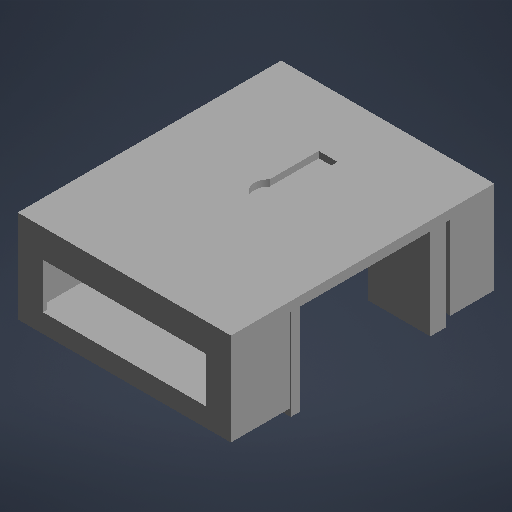
# Autodesk Inventor part: R2_pelvis
Saved by Autodesk Inventor 2027 (Build 310192060, 192F)
## iProperties
Part Number: R2_pelvis
Material: Genérico
Document SubType Name: Modelado
Designer: rodri
Appearance: Por defecto
Author: rodri
Autodesk Inventor part; units mm, degrees
ref_plane "Plano de trabajo1" through (0, 0, -38) normal (0, 0, 1) x (1, 0, 0)
sketch "Boceto1" plane through (0, 0, -38) normal (0, 0, 1) x (1, 0, 0)
  line L0 (-34, -3) -> (34, -3)
  line L1 (34, -3) -> (34, 0)
  line L2 (34, 0) -> (-34, 0)
  line L3 (-34, 0) -> (-34, -3)
  constraints: 8 end point, 2 parallel, 1 horizontal, 1 perpendicular
extrude "Extrusión1" add sketch "Boceto1" along normal blind 84
ref_plane "Plano de trabajo2" through (0, -2, 0) normal (0, 1, 0) x (-1, 0, 0)
sketch "Boceto2" plane through (0, -2, 0) normal (0, 1, 0) x (-1, 0, 0)
  circle A0 centre (0, 0) radius 4.5
  constraints: 1 centre point
extrude "Extrusión2" cut sketch "Boceto2" along normal blind 2.1
ref_plane "Plano de trabajo3" through (0, 0, -19) normal (0, 0, 1) x (1, 0, 0)
sketch "Boceto3" plane through (0, 0, -19) normal (0, 0, 1) x (1, 0, 0)
  line L0 (-3, -2) -> (3, -2)
  line L1 (3, -2) -> (3, 0.1)
  line L2 (3, 0.1) -> (-3, 0.1)
  line L3 (-3, 0.1) -> (-3, -2)
  constraints: 8 end point, 2 parallel, 1 horizontal, 1 perpendicular
extrude "Extrusión3" cut sketch "Boceto3" along normal blind 22
ref_plane "Plano de trabajo4" through (0, 0, 44.5) normal (0, 0, 1) x (1, 0, 0)
sketch "Boceto4" plane through (0, 0, 44.5) normal (0, 0, 1) x (1, 0, 0)
  line L0 (-34, -29.5) -> (34, -29.5)
  line L1 (34, -29.5) -> (34, -2.9)
  line L2 (34, -2.9) -> (-34, -2.9)
  line L3 (-34, -2.9) -> (-34, -29.5)
  constraints: 8 end point, 2 parallel, 1 horizontal, 1 perpendicular
extrude "Extrusión4" add sketch "Boceto4" along normal blind 1.5
ref_plane "Plano de trabajo5" through (0, 0, 27) normal (0, 0, 1) x (1, 0, 0)
sketch "Boceto5" plane through (0, 0, 27) normal (0, 0, 1) x (1, 0, 0)
  line L0 (-34, -29.5) -> (34, -29.5)
  line L1 (34, -29.5) -> (34, -27)
  line L2 (34, -27) -> (-34, -27)
  line L3 (-34, -27) -> (-34, -29.5)
  constraints: 8 end point, 2 parallel, 1 horizontal, 1 perpendicular
extrude "Extrusión5" add sketch "Boceto5" along normal blind 19
ref_plane "Plano de trabajo6" through (0, 0, 27) normal (0, 0, 1) x (1, 0, 0)
sketch "Boceto6" plane through (0, 0, 27) normal (0, 0, 1) x (1, 0, 0)
  line L0 (-34, -29.5) -> (-31.5, -29.5)
  line L1 (-31.5, -29.5) -> (-31.5, -2.9)
  line L2 (-31.5, -2.9) -> (-34, -2.9)
  line L3 (-34, -2.9) -> (-34, -29.5)
  constraints: 8 end point, 2 parallel, 1 horizontal, 1 perpendicular
extrude "Extrusión6" add sketch "Boceto6" along normal blind 19
ref_plane "Plano de trabajo7" through (0, 0, 27) normal (0, 0, 1) x (1, 0, 0)
sketch "Boceto7" plane through (0, 0, 27) normal (0, 0, 1) x (1, 0, 0)
  line L0 (31.5, -29.5) -> (34, -29.5)
  line L1 (34, -29.5) -> (34, -2.9)
  line L2 (34, -2.9) -> (31.5, -2.9)
  line L3 (31.5, -2.9) -> (31.5, -29.5)
  constraints: 8 end point, 2 parallel, 1 horizontal, 1 perpendicular
extrude "Extrusión7" add sketch "Boceto7" along normal blind 19
ref_plane "Plano de trabajo8" through (0, 0, 44.4) normal (0, 0, 1) x (1, 0, 0)
sketch "Boceto8" plane through (0, 0, 44.4) normal (0, 0, 1) x (1, 0, 0)
  line L0 (-26, -23.5) -> (26, -23.5)
  line L1 (26, -23.5) -> (26, -9)
  line L2 (26, -9) -> (-26, -9)
  line L3 (-26, -9) -> (-26, -23.5)
  constraints: 8 end point, 2 parallel, 1 horizontal, 1 perpendicular
extrude "Extrusión8" cut sketch "Boceto8" along normal blind 1.7
ref_plane "Plano de trabajo9" through (0, 0, -38) normal (0, 0, 1) x (1, 0, 0)
sketch "Boceto9" plane through (0, 0, -38) normal (0, 0, 1) x (1, 0, 0)
  line L0 (-34, -29.5) -> (34, -29.5)
  line L1 (34, -29.5) -> (34, -2.9)
  line L2 (34, -2.9) -> (-34, -2.9)
  line L3 (-34, -2.9) -> (-34, -29.5)
  constraints: 8 end point, 2 parallel, 1 horizontal, 1 perpendicular
extrude "Extrusión9" add sketch "Boceto9" along normal blind 2
ref_plane "Plano de trabajo10" through (0, 0, -38) normal (0, 0, 1) x (1, 0, 0)
sketch "Boceto10" plane through (0, 0, -38) normal (0, 0, 1) x (1, 0, 0)
  line L0 (-34, -29.5) -> (34, -29.5)
  line L1 (34, -29.5) -> (34, -27)
  line L2 (34, -27) -> (-34, -27)
  line L3 (-34, -27) -> (-34, -29.5)
  constraints: 8 end point, 2 parallel, 1 horizontal, 1 perpendicular
extrude "Extrusión10" add sketch "Boceto10" along normal blind 14
ref_plane "Plano de trabajo11" through (0, 0, -38) normal (0, 0, 1) x (1, 0, 0)
sketch "Boceto11" plane through (0, 0, -38) normal (0, 0, 1) x (1, 0, 0)
  line L0 (-34, -29.5) -> (-31.5, -29.5)
  line L1 (-31.5, -29.5) -> (-31.5, -2.9)
  line L2 (-31.5, -2.9) -> (-34, -2.9)
  line L3 (-34, -2.9) -> (-34, -29.5)
  constraints: 8 end point, 2 parallel, 1 horizontal, 1 perpendicular
extrude "Extrusión11" add sketch "Boceto11" along normal blind 14
ref_plane "Plano de trabajo12" through (0, 0, -38) normal (0, 0, 1) x (1, 0, 0)
sketch "Boceto12" plane through (0, 0, -38) normal (0, 0, 1) x (1, 0, 0)
  line L0 (31.5, -29.5) -> (34, -29.5)
  line L1 (34, -29.5) -> (34, -2.9)
  line L2 (34, -2.9) -> (31.5, -2.9)
  line L3 (31.5, -2.9) -> (31.5, -29.5)
  constraints: 8 end point, 2 parallel, 1 horizontal, 1 perpendicular
extrude "Extrusión12" add sketch "Boceto12" along normal blind 14
ref_plane "Plano de trabajo13" through (0, 0, -38.1) normal (0, 0, 1) x (1, 0, 0)
sketch "Boceto13" plane through (0, 0, -38.1) normal (0, 0, 1) x (1, 0, 0)
  line L0 (-26, -23.5) -> (26, -23.5)
  line L1 (26, -23.5) -> (26, -9)
  line L2 (26, -9) -> (-26, -9)
  line L3 (-26, -9) -> (-26, -23.5)
  constraints: 8 end point, 2 parallel, 1 horizontal, 1 perpendicular
extrude "Extrusión13" cut sketch "Boceto13" along normal blind 2.2
ref_plane "Plano de trabajo14" through (0, 0, -22.6) normal (0, 0, 1) x (1, 0, 0)
sketch "Boceto14" plane through (0, 0, -22.6) normal (0, 0, 1) x (1, 0, 0)
  line L0 (14, -32) -> (34, -32)
  line L1 (34, -32) -> (34, -0.01)
  line L2 (34, -0.01) -> (14, -0.01)
  line L3 (14, -0.01) -> (14, -32)
  constraints: 8 end point, 2 parallel, 1 horizontal, 1 perpendicular
extrude "Extrusión14" add sketch "Boceto14" along normal blind 4.99
ref_plane "Plano de trabajo15" through (0, 0, -22.6) normal (0, 0, 1) x (1, 0, 0)
sketch "Boceto15" plane through (0, 0, -22.6) normal (0, 0, 1) x (1, 0, 0)
  circle A0 centre (24, -22) radius 10
  constraints: 1 centre point
extrude "Extrusión15" add sketch "Boceto15" along normal blind 4.99
ref_plane "Plano de trabajo16" through (0, 0, 23.92) normal (0, 0, 1) x (1, 0, 0)
sketch "Boceto16" plane through (0, 0, 23.92) normal (0, 0, 1) x (1, 0, 0)
  line L0 (14, -32) -> (34, -32)
  line L1 (34, -32) -> (34, -0.01)
  line L2 (34, -0.01) -> (14, -0.01)
  line L3 (14, -0.01) -> (14, -32)
  constraints: 8 end point, 2 parallel, 1 horizontal, 1 perpendicular
extrude "Extrusión16" add sketch "Boceto16" along normal blind 3
ref_plane "Plano de trabajo17" through (0, 0, 23.92) normal (0, 0, 1) x (1, 0, 0)
sketch "Boceto17" plane through (0, 0, 23.92) normal (0, 0, 1) x (1, 0, 0)
  circle A0 centre (24, -22) radius 10
  constraints: 1 centre point
extrude "Extrusión17" add sketch "Boceto17" along normal blind 3
ref_plane "Plano de trabajo18" through (0, 0, -22.7) normal (0, 0, 1) x (1, 0, 0)
sketch "Boceto18" plane through (0, 0, -22.7) normal (0, 0, 1) x (1, 0, 0)
  circle A0 centre (24, -22) radius 4.2
  constraints: 1 centre point
extrude "Extrusión18" cut sketch "Boceto18" along normal blind 3.2
ref_plane "Plano de trabajo19" through (0, 0, 23.81) normal (0, 0, 1) x (1, 0, 0)
sketch "Boceto19" plane through (0, 0, 23.81) normal (0, 0, 1) x (1, 0, 0)
  circle A0 centre (24, -22) radius 3.15
  constraints: 1 centre point
extrude "Extrusión19" cut sketch "Boceto19" along normal blind 3.2
ref_plane "Plano de trabajo20" through (0, 0, -22.6) normal (0, 0, 1) x (1, 0, 0)
sketch "Boceto20" plane through (0, 0, -22.6) normal (0, 0, 1) x (1, 0, 0)
  line L0 (-34, -32) -> (-14, -32)
  line L1 (-14, -32) -> (-14, -0.01)
  line L2 (-14, -0.01) -> (-34, -0.01)
  line L3 (-34, -0.01) -> (-34, -32)
  constraints: 8 end point, 2 parallel, 1 horizontal, 1 perpendicular
extrude "Extrusión20" add sketch "Boceto20" along normal blind 4.99
ref_plane "Plano de trabajo21" through (0, 0, -22.6) normal (0, 0, 1) x (1, 0, 0)
sketch "Boceto21" plane through (0, 0, -22.6) normal (0, 0, 1) x (1, 0, 0)
  circle A0 centre (-24, -22) radius 10
  constraints: 1 centre point
extrude "Extrusión21" add sketch "Boceto21" along normal blind 4.99
ref_plane "Plano de trabajo22" through (0, 0, 23.92) normal (0, 0, 1) x (1, 0, 0)
sketch "Boceto22" plane through (0, 0, 23.92) normal (0, 0, 1) x (1, 0, 0)
  line L0 (-34, -32) -> (-14, -32)
  line L1 (-14, -32) -> (-14, -0.01)
  line L2 (-14, -0.01) -> (-34, -0.01)
  line L3 (-34, -0.01) -> (-34, -32)
  constraints: 8 end point, 2 parallel, 1 horizontal, 1 perpendicular
extrude "Extrusión22" add sketch "Boceto22" along normal blind 3
ref_plane "Plano de trabajo23" through (0, 0, 23.92) normal (0, 0, 1) x (1, 0, 0)
sketch "Boceto23" plane through (0, 0, 23.92) normal (0, 0, 1) x (1, 0, 0)
  circle A0 centre (-24, -22) radius 10
  constraints: 1 centre point
extrude "Extrusión23" add sketch "Boceto23" along normal blind 3
ref_plane "Plano de trabajo24" through (0, 0, -22.7) normal (0, 0, 1) x (1, 0, 0)
sketch "Boceto24" plane through (0, 0, -22.7) normal (0, 0, 1) x (1, 0, 0)
  circle A0 centre (-24, -22) radius 4.2
  constraints: 1 centre point
extrude "Extrusión24" cut sketch "Boceto24" along normal blind 3.2
ref_plane "Plano de trabajo25" through (0, 0, 23.81) normal (0, 0, 1) x (1, 0, 0)
sketch "Boceto25" plane through (0, 0, 23.81) normal (0, 0, 1) x (1, 0, 0)
  circle A0 centre (-24, -22) radius 3.15
  constraints: 1 centre point
extrude "Extrusión25" cut sketch "Boceto25" along normal blind 3.2
